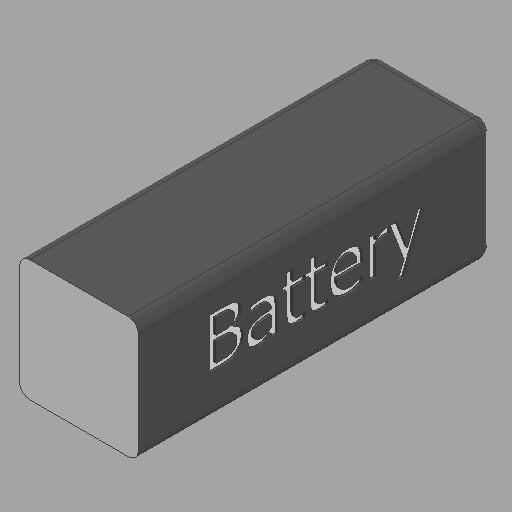
# Autodesk Inventor part: Battery
Saved by Autodesk Inventor 2025 (Build 290162000, 162)
## iProperties
Created: 2024-11-04
Part Number: Battery
Material: 일반
Document SubType Name: Modeling
Designer: OSB
Density: 1.51262 g/cm^3
Appearance: 기본값
Mass: 473 g
Surface Area: 303.459 cm^2
Volume: 312.702 cm^3
Author: OSB
Autodesk Inventor part; units mm, degrees
ref_plane "YZ Plane" through (0, 0, 0) normal (1, 0, 0) x (0, 1, 0)
ref_plane "XZ Plane" through (0, 0, 0) normal (0, 1, 0) x (-1, 0, 0)
ref_plane "XY Plane" through (0, 0, 0) normal (0, 0, 1) x (1, 0, 0)
sketch "스케치1" plane through (0, 0, 0) normal (1, 0, 0) x (0, 1, 0)
  line L0 (-23.5, 24) -> (23.5, 24)
  line L1 (23.5, 24) -> (23.5, -24)
  line L2 (23.5, -24) -> (-23.5, -24)
  line L3 (-23.5, -24) -> (-23.5, 24)
  line L4 (-23.5, 24) -> (23.5, -24) construction
  line L5 (23.5, 24) -> (-23.5, -24) construction
  point P0 (0, 0)
  dimension "d0" = 47
  dimension "d1" = 48
  constraints: 12 end point, 2 midpoint, 2 parallel, 1 horizontal, 1 perpendicular
  measures "d0" distance of L1.end L2.end
  measures "d1" distance of L0.end L1.end
extrude "돌출1" add sketch "스케치1" along normal blind 140
fillet "모깎기1" radius 4 8 edges at (70, 23.5, 24) (70, -23.5, 24) (70, 23.5, -24) (0, 23.5, 0) (0, 0, -24) (0, -23.5, 0) (0, 0, 24) (70, -23.5, -24)
sketch "스케치2" plane through (4, 23.5, 20) normal (0, 1, 0) x (1, 0, 0)
  line L0 (109.8982, 7.6393) -> (26.2952, 7.6393) construction
  line L1 (26.2952, 7.6393) -> (26.2952, 24.6803) construction
  line L2 (26.2952, 24.6803) -> (109.8982, 24.6803) construction
  line L3 (109.8982, 24.6803) -> (109.8982, 7.6393) construction
  spline S0 degree 2 poles (94.3066, 21.4967) (94.3066, 22.9878) (95.4412, 25.273) (96.3812, 26.0186) knots 0 0 0 1 2 2 2
  spline S1 degree 2 poles (96.3812, 26.0186) (97.5157, 26.8938) (100.0927, 27.6393) (102.1348, 27.6393) knots 0 0 0 1 2 2 2
  line L4 (102.1348, 27.6393) -> (107.8723, 27.6393)
  line L5 (107.8723, 27.6393) -> (107.8723, 7.6393)
  line L6 (107.8723, 7.6393) -> (102.5724, 7.6393)
  spline S2 degree 2 poles (102.5724, 7.6393) (100.433, 7.6393) (98.2937, 7.9148) (97.3212, 8.4497) knots 0 0 0 1 2 2 2
  spline S3 degree 2 poles (97.3212, 8.4497) (96.2353, 9.0169) (95.2467, 10.8808) (95.2467, 12.145) knots 0 0 0 1 2 2 2
  spline S4 degree 2 poles (95.2467, 12.145) (95.2467, 13.555) (96.7377, 15.7917) (98.0506, 16.4238) knots 0 0 0 1 2 2 2
  line L7 (98.0506, 16.4238) -> (98.0506, 16.521)
  spline S5 degree 2 poles (98.0506, 16.521) (96.2677, 17.0072) (94.3066, 19.5842) (94.3066, 21.4967) knots 0 0 0 1 2 2 2
  spline S6 degree 2 poles (97.0781, 21.6101) (97.0781, 20.4756) (97.7264, 19.0169) (98.6989, 18.4983) knots 0 0 0 1 2 2 2
  spline S7 degree 2 poles (98.6989, 18.4983) (99.3309, 18.1742) (100.822, 17.9797) (102.1997, 17.9797) knots 0 0 0 1 2 2 2
  line L8 (102.1997, 17.9797) -> (105.2142, 17.9797)
  line L9 (105.2142, 17.9797) -> (105.2142, 25.3703)
  line L10 (105.2142, 25.3703) -> (103.0587, 25.3703)
  spline S8 degree 2 poles (103.0587, 25.3703) (101.3083, 25.3703) (99.2985, 25.0461) (98.5206, 24.5275) knots 0 0 0 1 2 2 2
  spline S9 degree 2 poles (98.5206, 24.5275) (97.775, 23.9926) (97.0781, 22.6636) (97.0781, 21.6101) knots 0 0 0 1 2 2 2
  spline S10 degree 2 poles (98.0181, 12.5178) (98.0181, 11.8046) (98.5044, 10.7349) (99.0392, 10.427) knots 0 0 0 1 2 2 2
  spline S11 degree 2 poles (99.0392, 10.427) (99.6875, 10.0704) (101.2596, 9.9084) (102.6697, 9.9084) knots 0 0 0 1 2 2 2
  line L11 (102.6697, 9.9084) -> (105.2142, 9.9084)
  line L12 (105.2142, 9.9084) -> (105.2142, 15.7592)
  line L13 (105.2142, 15.7592) -> (102.1997, 15.7592)
  spline S12 degree 2 poles (102.1997, 15.7592) (100.9517, 15.7592) (99.7685, 15.4999) (99.1365, 15.0947) knots 0 0 0 1 2 2 2
  spline S13 degree 2 poles (99.1365, 15.0947) (98.5206, 14.7058) (98.0181, 13.4578) (98.0181, 12.5178) knots 0 0 0 1 2 2 2
  spline S14 degree 2 poles (83.4963, 26.051) (83.8042, 26.2779) (84.8415, 27.0883) (85.3277, 27.3314) knots 0 0 0 1 2 2 2
  spline S15 degree 2 poles (85.3277, 27.3314) (85.9922, 27.6879) (87.2402, 28.0607) (88.3747, 28.0607) knots 0 0 0 1 2 2 2
  spline S16 degree 2 poles (88.3747, 28.0607) (89.2985, 28.0607) (90.9679, 27.3638) (91.6, 26.7317) knots 0 0 0 1 2 2 2
  spline S17 degree 2 poles (91.6, 26.7317) (92.1997, 26.1158) (92.929, 24.3006) (92.929, 23.2957) knots 0 0 0 1 2 2 2
  spline S18 degree 2 poles (92.929, 23.2957) (92.929, 21.7398) (91.6162, 19.5356) (90.1899, 18.9035) knots 0 0 0 1 2 2 2
  spline S19 degree 2 poles (90.1899, 18.9035) (88.9258, 18.32) (85.4898, 17.8824) (83.4963, 17.769) knots 0 0 0 1 2 2 2
  line L14 (83.4963, 17.769) -> (83.4963, 17.2827)
  spline S20 degree 2 poles (83.4963, 17.2827) (83.4963, 16.4075) (84.0311, 15.3216) (84.5173, 15.0137) knots 0 0 0 1 2 2 2
  spline S21 degree 2 poles (84.5173, 15.0137) (85.0036, 14.7058) (86.3974, 14.5113) (87.1429, 14.5113) knots 0 0 0 1 2 2 2
  spline S22 degree 2 poles (87.1429, 14.5113) (88.0181, 14.5113) (90.3844, 15.0299) (91.5676, 15.5323) knots 0 0 0 1 2 2 2
  line L15 (91.5676, 15.5323) -> (91.7134, 15.5323)
  line L16 (91.7134, 15.5323) -> (91.7134, 12.9554)
  spline S23 degree 2 poles (91.7134, 12.9554) (91.0165, 12.7609) (88.4071, 12.2746) (87.1267, 12.2746) knots 0 0 0 1 2 2 2
  spline S24 degree 2 poles (87.1267, 12.2746) (85.5708, 12.2746) (83.4476, 12.7609) (82.6048, 13.393) knots 0 0 0 1 2 2 2
  spline S25 degree 2 poles (82.6048, 13.393) (81.7783, 14.0088) (80.9679, 15.9699) (80.9679, 17.38) knots 0 0 0 1 2 2 2
  line L17 (80.9679, 17.38) -> (80.9679, 27.6393)
  line L18 (80.9679, 27.6393) -> (83.4963, 27.6393)
  line L19 (83.4963, 27.6393) -> (83.4963, 26.051)
  line L20 (83.4963, 23.944) -> (83.4963, 19.7787)
  spline S26 degree 2 poles (83.4963, 19.7787) (84.4039, 19.8597) (87.1429, 20.1353) (88.0019, 20.3946) knots 0 0 0 1 2 2 2
  spline S27 degree 2 poles (88.0019, 20.3946) (89.0068, 20.7025) (90.3196, 21.9829) (90.3196, 23.1174) knots 0 0 0 1 2 2 2
  spline S28 degree 2 poles (90.3196, 23.1174) (90.3196, 24.414) (88.8609, 25.7268) (87.4671, 25.7268) knots 0 0 0 1 2 2 2
  spline S29 degree 2 poles (87.4671, 25.7268) (86.2839, 25.7268) (84.339, 24.7058) (83.4963, 23.944) knots 0 0 0 1 2 2 2
  spline S30 degree 2 poles (72.8804, 27.931) (74.9387, 27.931) (77.2564, 25.581) (77.2564, 23.0364) knots 0 0 0 1 2 2 2
  line L21 (77.2564, 23.0364) -> (77.2564, 14.722)
  line L22 (77.2564, 14.722) -> (78.9582, 14.722)
  line L23 (78.9582, 14.722) -> (78.9582, 12.6312)
  line L24 (78.9582, 12.6312) -> (77.2564, 12.6312)
  line L25 (77.2564, 12.6312) -> (77.2564, 8.32)
  line L26 (77.2564, 8.32) -> (74.728, 8.32)
  line L27 (74.728, 8.32) -> (74.728, 12.6312)
  line L28 (74.728, 12.6312) -> (70.0765, 12.6312)
  line L29 (70.0765, 12.6312) -> (70.0765, 14.722)
  line L30 (70.0765, 14.722) -> (74.728, 14.722)
  line L31 (74.728, 14.722) -> (74.728, 21.8695)
  spline S31 degree 2 poles (74.728, 21.8695) (74.728, 23.004) (74.647, 24.252) (74.3715, 24.7868) knots 0 0 0 1 2 2 2
  spline S32 degree 2 poles (74.3715, 24.7868) (74.1446, 25.2568) (73.1235, 25.7268) (72.2483, 25.7268) knots 0 0 0 1 2 2 2
  spline S33 degree 2 poles (72.2483, 25.7268) (71.6324, 25.7268) (70.4817, 25.3541) (70.2224, 25.2406) knots 0 0 0 1 2 2 2
  line L32 (70.2224, 25.2406) -> (70.0765, 25.2406)
  line L33 (70.0765, 25.2406) -> (70.0765, 27.5097)
  spline S34 degree 2 poles (70.0765, 27.5097) (70.7896, 27.7041) (72.2483, 27.931) (72.8804, 27.931) knots 0 0 0 1 2 2 2
  spline S35 degree 2 poles (63.6745, 27.931) (65.7329, 27.931) (68.0506, 25.581) (68.0506, 23.0364) knots 0 0 0 1 2 2 2
  line L34 (68.0506, 23.0364) -> (68.0506, 14.722)
  line L35 (68.0506, 14.722) -> (69.7523, 14.722)
  line L36 (69.7523, 14.722) -> (69.7523, 12.6312)
  line L37 (69.7523, 12.6312) -> (68.0506, 12.6312)
  line L38 (68.0506, 12.6312) -> (68.0506, 8.32)
  line L39 (68.0506, 8.32) -> (65.5222, 8.32)
  line L40 (65.5222, 8.32) -> (65.5222, 12.6312)
  line L41 (65.5222, 12.6312) -> (60.8707, 12.6312)
  line L42 (60.8707, 12.6312) -> (60.8707, 14.722)
  line L43 (60.8707, 14.722) -> (65.5222, 14.722)
  line L44 (65.5222, 14.722) -> (65.5222, 21.8695)
  spline S36 degree 2 poles (65.5222, 21.8695) (65.5222, 23.004) (65.4412, 24.252) (65.1656, 24.7868) knots 0 0 0 1 2 2 2
  spline S37 degree 2 poles (65.1656, 24.7868) (64.9387, 25.2568) (63.9177, 25.7268) (63.0424, 25.7268) knots 0 0 0 1 2 2 2
  spline S38 degree 2 poles (63.0424, 25.7268) (62.4266, 25.7268) (61.2758, 25.3541) (61.0165, 25.2406) knots 0 0 0 1 2 2 2
  line L45 (61.0165, 25.2406) -> (60.8707, 25.2406)
  line L46 (60.8707, 25.2406) -> (60.8707, 27.5097)
  spline S39 degree 2 poles (60.8707, 27.5097) (61.5838, 27.7041) (63.0424, 27.931) (63.6745, 27.931) knots 0 0 0 1 2 2 2
  spline S40 degree 2 poles (52.4914, 27.9797) (56.0895, 27.9797) (60.0441, 23.944) (60.0441, 20.2163) knots 0 0 0 1 2 2 2
  spline S41 degree 2 poles (60.0441, 20.2163) (60.0441, 16.5534) (56.2029, 12.2098) (53.1073, 12.2098) knots 0 0 0 1 2 2 2
  spline S42 degree 2 poles (53.1073, 12.2098) (51.7134, 12.2098) (49.5578, 13.0202) (48.7637, 13.8792) knots 0 0 0 1 2 2 2
  spline S43 degree 2 poles (48.7637, 13.8792) (47.9533, 14.7382) (47.0943, 17.2179) (47.0943, 19.0169) knots 0 0 0 1 2 2 2
  line L47 (47.0943, 19.0169) -> (47.0943, 20.3946)
  line L48 (47.0943, 20.3946) -> (57.4833, 20.3946)
  spline S44 degree 2 poles (57.4833, 20.3946) (57.4833, 23.004) (54.8577, 25.7755) (52.5238, 25.7755) knots 0 0 0 1 2 2 2
  spline S45 degree 2 poles (52.5238, 25.7755) (51.6972, 25.7755) (50.0927, 25.4027) (49.4444, 25.1109) knots 0 0 0 1 2 2 2
  spline S46 degree 2 poles (49.4444, 25.1109) (48.7637, 24.7868) (47.8236, 24.2195) (47.5157, 23.9602) knots 0 0 0 1 2 2 2
  line L49 (47.5157, 23.9602) -> (47.3698, 23.9602)
  line L50 (47.3698, 23.9602) -> (47.3698, 26.7155)
  spline S47 degree 2 poles (47.3698, 26.7155) (47.8074, 26.8938) (49.1365, 27.4124) (49.6551, 27.5583) knots 0 0 0 1 2 2 2
  spline S48 degree 2 poles (49.6551, 27.5583) (50.3844, 27.769) (51.5838, 27.9797) (52.4914, 27.9797) knots 0 0 0 1 2 2 2
  spline S49 degree 2 poles (49.5578, 18.4659) (49.5903, 17.4448) (50.0117, 15.9537) (50.4168, 15.4513) knots 0 0 0 1 2 2 2
  spline S50 degree 2 poles (50.4168, 15.4513) (50.8544, 14.884) (52.2321, 14.2844) (53.2531, 14.2844) knots 0 0 0 1 2 2 2
  spline S51 degree 2 poles (53.2531, 14.2844) (54.258, 14.2844) (55.6681, 14.884) (56.2515, 15.4675) knots 0 0 0 1 2 2 2
  spline S52 degree 2 poles (56.2515, 15.4675) (56.8188, 16.0672) (57.4023, 17.5097) (57.4833, 18.4659) knots 0 0 0 1 2 2 2
  line L51 (57.4833, 18.4659) -> (49.5578, 18.4659)
  line L52 (36.5757, 15.3379) -> (36.7053, 15.3379)
  spline S53 degree 2 poles (36.7053, 15.3379) (36.9971, 15.2568) (37.6292, 15.2244) (38.0668, 15.2244) knots 0 0 0 1 2 2 2
  spline S54 degree 2 poles (38.0668, 15.2244) (39.0878, 15.2244) (41.0976, 16.1158) (42.0052, 16.991) knots 0 0 0 1 2 2 2
  line L53 (42.0052, 16.991) -> (42.0052, 27.6393)
  line L54 (42.0052, 27.6393) -> (44.5335, 27.6393)
  line L55 (44.5335, 27.6393) -> (44.5335, 12.6312)
  line L56 (44.5335, 12.6312) -> (42.0052, 12.6312)
  line L57 (42.0052, 12.6312) -> (42.0052, 14.8678)
  spline S55 degree 2 poles (42.0052, 14.8678) (40.6275, 13.6361) (38.5692, 12.6312) (37.5967, 12.6312) knots 0 0 0 1 2 2 2
  spline S56 degree 2 poles (37.5967, 12.6312) (37.2078, 12.6312) (36.8188, 12.6636) (36.5757, 12.7122) knots 0 0 0 1 2 2 2
  line L58 (36.5757, 12.7122) -> (36.5757, 15.3379)
  line L59 (22.8318, 12.6312) -> (30.9031, 33.1661)
  line L60 (30.9031, 33.1661) -> (33.6097, 33.1661)
  line L61 (33.6097, 33.1661) -> (30.9193, 26.91)
  line L62 (30.9193, 26.91) -> (36.365, 12.6312)
  line L63 (36.365, 12.6312) -> (33.6421, 12.6312)
  line L64 (33.6421, 12.6312) -> (29.5416, 23.7495)
  line L65 (29.5416, 23.7495) -> (25.4574, 12.6312)
  line L66 (25.4574, 12.6312) -> (22.8318, 12.6312)
  point P0 (-4, 20)
  constraints: 2 other
emboss "엠보싱1" sketch "스케치2" operation cut depth 1 direction (0, -1, 0)
